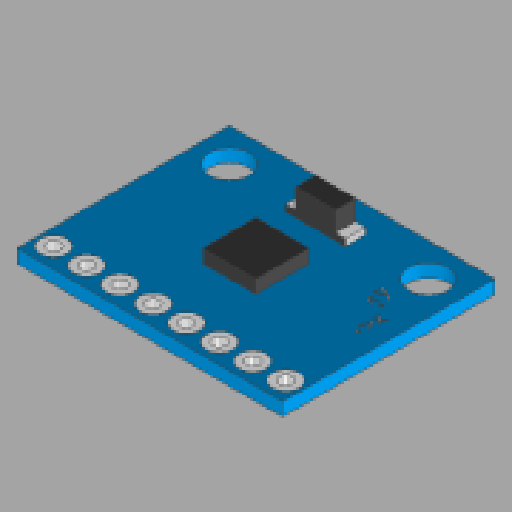
# Autodesk Inventor part: MPU6050_my
Saved by Autodesk Inventor 2025 (Build 290162000, 162)
## iProperties
Created: 2024-11-10
Part Number: MPU6050_my
Material: 일반
Document SubType Name: Modeling
Designer: OSB
Density: 1 g/cm^3
Appearance: 기본값
Author: OSB
Autodesk Inventor part; units mm, degrees
ref_plane "YZ Plane" through (0, 0, 0) normal (1, 0, 0) x (0, 1, 0)
ref_plane "XZ Plane" through (0, 0, 0) normal (0, 1, 0) x (-1, 0, 0)
ref_plane "XY Plane" through (0, 0, 0) normal (0, 0, 1) x (1, 0, 0)
sketch "스케치1" plane through (0, 0, 0) normal (0, 0, 1) x (1, 0, 0)
  line L0 (8, -10) -> (-8, -10)
  line L1 (-8, -10) -> (-8, 10)
  line L2 (-8, 10) -> (8, 10)
  line L3 (8, 10) -> (8, -10)
  line L4 (8, -10) -> (-8, 10) construction
  line L5 (-8, -10) -> (8, 10) construction
  circle A0 centre (-5.5, -7.5) radius 1.5
  circle A1 centre (-5.5, 7.5) radius 1.5
  circle A2 centre (6.5, -8.75) radius 0.5
  circle A3 centre (6.5, -6.25) radius 0.5
  circle A4 centre (6.5, -3.75) radius 0.5
  circle A5 centre (6.5, -1.25) radius 0.5
  circle A6 centre (6.5, 1.25) radius 0.5
  circle A7 centre (6.5, 3.75) radius 0.5
  circle A8 centre (6.5, 6.25) radius 0.5
  circle A9 centre (6.5, 8.75) radius 0.5
  line L6 (-4.5, 2.25) -> (-6, 2.25)
  line L7 (-6, 2.25) -> (-6, -2.25)
  line L8 (-6, -2.25) -> (-4.5, -2.25)
  line L9 (-4.5, -2.25) -> (-4.5, 2.25)
  line L10 (-4.5, 2.25) -> (-6, -2.25) construction
  line L11 (-6, 2.25) -> (-4.5, -2.25) construction
  line L12 (-4.5, 1.5) -> (-6, 1.5)
  line L13 (-4.5, -1.5) -> (-6, -1.5)
  line L14 (-2, 2) -> (2, 2)
  line L15 (2, 2) -> (2, -2)
  line L16 (2, -2) -> (-2, -2)
  line L17 (-2, -2) -> (-2, 2)
  line L18 (-2, 2) -> (2, -2) construction
  line L19 (2, 2) -> (-2, -2) construction
  point P0 (0, 0)
  point P1 (-5.25, 0)
  point P2 (-5.25, -2.25)
  dimension "d0" = 16
  dimension "d1" = 20
  dimension "d2" = 3
  dimension "d3" = 3
  dimension "d4" = 2.5
  dimension "d8" = 2.5
  dimension "d9" = 12
  dimension "d10" = 1
  dimension "d11" = 1.5
  dimension "d14" = 2.5
  dimension "d19" = 1.25
  dimension "d20" = 1.25
  dimension "d24" = 4.5
  dimension "d25" = 2
  dimension "d26" = 1.5
  dimension "d27" = 0.75
  dimension "d28" = 0.75
  dimension "d47" = 4
  dimension "d48" = 4
  constraints: 40 end point, 10 centre point, 7 midpoint, 6 parallel, 5 perpendicular, 4 point on line, 3 horizontal, 1 horizontal alignment, 1 vertical, 1 vertical alignment, 14 other
  measures "d0" distance of L1.end L2.end
  measures "d1" distance of L0.end L1.end
  measures "d2" diameter of A0
  measures "d3" diameter of A1
  measures "d4" distance from line of L0 A0.centre
  measures "d8" distance from line of A0.centre L1
  measures "d10" diameter of A2
  measures "d11" distance from line of L3 A2.centre
  measures "d14" distance of A2.centre A3.centre
  measures "d19" distance from line of L0 A2.centre
  measures "d20" distance from line of L2 A9.centre
  measures "d24" distance between parallel lines of L6 L8
  measures "d25" distance between parallel lines of L1 L7
  measures "d26" distance of L6.start L6.end
  measures "d27" distance from line of point (-5.25, -2.25) L13
  measures "d28" distance between parallel lines of L6 L12
  measures "d47" distance of L15.end L16.end
  measures "d48" distance of L14.end L15.end
extrude "돌출1" add sketch "스케치1" along normal blind 1 contours L0 L1 L2 L3 | L9 L12 L7 L6 | L9 L13 L7 L12 | L9 L8 L7 L13 | L14 L15 L16 L17
extrude "돌출2" add sketch "스케치1" along normal blind 0.5 from surface at 1 contours L9 L12 L7 L6 | L9 L8 L7 L13
extrude "돌출3" add sketch "스케치1" along normal blind 2 from surface at 1 contours L9 L13 L7 L12
sketch "스케치3" plane through (0, 0, 1) normal (0, 0, 1) x (1, 0, 0)
  circle A0 centre (-5.5, 7.5) radius 1.5 projected
  line L0 (-8, 10) -> (-8, -10) projected
  line L1 (-8, -10) -> (8, -10) projected
  line L2 (8, -10) -> (8, 10) projected
  line L3 (8, 10) -> (-8, 10) projected
  line L4 (-4.5, 2.25) -> (-4.5, -2.25) projected
  line L5 (-4.5, -2.25) -> (-6, -2.25) projected
  line L6 (-6, -2.25) -> (-6, 2.25) projected
  line L7 (-6, 2.25) -> (-4.5, 2.25) projected
  circle A1 centre (6.5, 6.25) radius 0.5 projected
  circle A2 centre (6.5, -8.75) radius 0.5 projected
  circle A3 centre (6.5, -6.25) radius 0.5 projected
  circle A4 centre (6.5, -3.75) radius 0.5 projected
  circle A5 centre (6.5, -1.25) radius 0.5 projected
  circle A6 centre (6.5, 1.25) radius 0.5 projected
  circle A7 centre (6.5, 3.75) radius 0.5 projected
  circle A8 centre (6.5, 8.75) radius 0.5 projected
  circle A9 centre (-5.5, -7.5) radius 1.5 projected
  circle A10 centre (6.5, 8.75) radius 1
  circle A11 centre (6.5, 6.25) radius 1
  circle A12 centre (6.5, 3.75) radius 1
  circle A13 centre (6.5, 1.25) radius 1
  circle A14 centre (6.5, -1.25) radius 1
  circle A15 centre (6.5, -3.75) radius 1
  circle A16 centre (6.5, -6.25) radius 1
  circle A17 centre (6.5, -8.75) radius 1
  point P0 (0, 0)
  dimension "d33" = 2
  dimension "d36" = 2.5
  constraints: 8 centre point, 1 coincident, 1 vertical, 14 other
  measures "d33" diameter of A10
  measures "d36" distance of A10.centre A11.centre
extrude "돌출4" add sketch "스케치3" along normal blind 0.01 and the other way blind 1.01 contours A10 | A11 | A12 | A13 | A14 | A15 | A16 | A17
sketch "스케치4" plane through (0, 0, 1) normal (0, 0, 1) x (1, 0, 0)
  line L0 (0.8694, 7.894) -> (-1.9199, 7.894) construction
  line L1 (-1.9199, 7.894) -> (-1.9199, 8.844) construction
  line L2 (-1.9199, 8.844) -> (0.8694, 8.844) construction
  line L3 (0.8694, 8.844) -> (0.8694, 7.894) construction
  line L4 (-1.6198, 7.7515) -> (-1.6198, 6.2147) construction
  line L5 (-1.6198, 6.2147) -> (-2.317, 6.2147) construction
  line L6 (-2.317, 6.2147) -> (-2.317, 7.7515) construction
  line L7 (-2.317, 7.7515) -> (-1.6198, 7.7515) construction
  line L8 (-2.5384, 6.2759) -> (-3.2478, 6.2759) construction
  line L9 (-3.2478, 6.2759) -> (-3.2478, 7.226) construction
  line L10 (-3.2478, 7.226) -> (-2.5384, 7.226) construction
  line L11 (-2.5384, 7.226) -> (-2.5384, 6.2759) construction
  line L12 (-3.2159, 6.2759) -> (-2.8853, 7.1079)
  spline S0 degree 2 poles (-2.8853, 7.1079) (-2.7986, 7.3256) (-2.6432, 7.3256) knots 0 0 0 1 1 1
  spline S1 degree 2 poles (-2.6432, 7.3256) (-2.6062, 7.3256) (-2.5728, 7.3175) knots 0 0 0 1 1 1
  line L13 (-2.5728, 7.3175) -> (-2.5728, 7.219)
  spline S2 degree 2 poles (-2.5728, 7.219) (-2.6071, 7.2308) (-2.6387, 7.2308) knots 0 0 0 1 1 1
  spline S3 degree 2 poles (-2.6387, 7.2308) (-2.7254, 7.2308) (-2.7688, 7.126) knots 0 0 0 1 1 1
  line L14 (-2.7688, 7.126) -> (-2.8275, 6.9878)
  line L15 (-2.8275, 6.9878) -> (-2.5484, 6.2759)
  line L16 (-2.5484, 6.2759) -> (-2.6685, 6.2759)
  line L17 (-2.6685, 6.2759) -> (-2.8654, 6.8324)
  spline S4 degree 2 poles (-2.8654, 6.8324) (-2.8672, 6.8378) (-2.8799, 6.8839) knots 0 0 0 1 1 1
  line L18 (-2.8799, 6.8839) -> (-2.8835, 6.8839)
  line L19 (-2.8835, 6.8839) -> (-2.8971, 6.8342)
  line L20 (-2.8971, 6.8342) -> (-3.1039, 6.2759)
  line L21 (-3.1039, 6.2759) -> (-3.2159, 6.2759)
  line L22 (-2.0308, 7.2709) -> (-2.0308, 7.6512)
  line L23 (-2.0308, 7.6512) -> (-1.9441, 7.6512)
  line L24 (-1.9441, 7.6512) -> (-1.9441, 7.2709)
  line L25 (-1.9441, 7.2709) -> (-2.0308, 7.2709)
  line L26 (-1.9929, 6.3938) -> (-2.2946, 6.99)
  line L27 (-2.2946, 6.99) -> (-2.1952, 6.99)
  line L28 (-2.1952, 6.99) -> (-1.9757, 6.5428)
  line L29 (-1.9757, 6.5428) -> (-1.9712, 6.5428)
  line L30 (-1.9712, 6.5428) -> (-1.72, 6.99)
  line L31 (-1.72, 6.99) -> (-1.6198, 6.99)
  line L32 (-1.6198, 6.99) -> (-1.9576, 6.3938)
  line L33 (-1.9576, 6.3938) -> (-1.9929, 6.3938)
  line L34 (0.3889, 8.305) -> (0.7692, 8.305)
  line L35 (0.7692, 8.305) -> (0.7692, 8.2183)
  line L36 (0.7692, 8.2183) -> (0.3889, 8.2183)
  line L37 (0.3889, 8.2183) -> (0.3889, 8.305)
  line L38 (-0.4883, 8.2671) -> (0.1079, 8.5688)
  line L39 (0.1079, 8.5688) -> (0.1079, 8.4694)
  line L40 (0.1079, 8.4694) -> (-0.3392, 8.2499)
  line L41 (-0.3392, 8.2499) -> (-0.3392, 8.2454)
  line L42 (-0.3392, 8.2454) -> (0.1079, 7.9943)
  line L43 (0.1079, 7.9943) -> (0.1079, 7.894)
  line L44 (0.1079, 7.894) -> (-0.4883, 8.2318)
  line L45 (-0.4883, 8.2318) -> (-0.4883, 8.2671)
  line L46 (-1.3031, 7.9464) -> (-1.0637, 8.3086)
  line L47 (-1.0637, 8.3086) -> (-1.2995, 8.66)
  line L48 (-1.2995, 8.66) -> (-1.173, 8.66)
  line L49 (-1.173, 8.66) -> (-1.0312, 8.4261)
  spline S5 degree 2 poles (-1.0312, 8.4261) (-1.0158, 8.3999) (-1.0005, 8.3719) knots 0 0 0 1 1 1
  line L50 (-1.0005, 8.3719) -> (-0.9969, 8.3719)
  spline S6 degree 2 poles (-0.9969, 8.3719) (-0.9924, 8.3809) (-0.9653, 8.4261) knots 0 0 0 1 1 1
  line L51 (-0.9653, 8.4261) -> (-0.8189, 8.66)
  line L52 (-0.8189, 8.66) -> (-0.6952, 8.66)
  line L53 (-0.6952, 8.66) -> (-0.9391, 8.3104)
  line L54 (-0.9391, 8.3104) -> (-0.7051, 7.9464)
  line L55 (-0.7051, 7.9464) -> (-0.8307, 7.9464)
  line L56 (-0.8307, 7.9464) -> (-1.0005, 8.2481)
  line L57 (-1.0005, 8.2481) -> (-1.0032, 8.2481)
  spline S7 degree 2 poles (-1.0032, 8.2481) (-1.0077, 8.2418) (-1.033, 8.1993) knots 0 0 0 1 1 1
  line L58 (-1.033, 8.1993) -> (-1.1857, 7.9464)
  line L59 (-1.1857, 7.9464) -> (-1.3031, 7.9464)
  point P0 (0, 0)
  constraints: 6 other
extrude "돌출5" add sketch "스케치4" along normal blind 0.01
extrude "돌출6" add sketch "스케치1" along normal blind 1 from surface at 1 contours L14 L15 L16 L17
